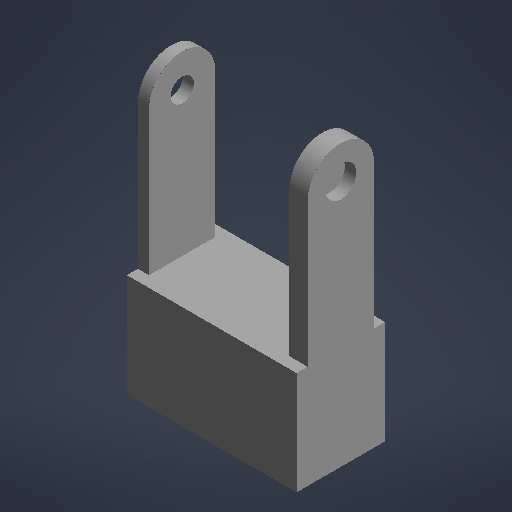
# Autodesk Inventor part: R2_antebrazo_izq
Saved by Autodesk Inventor 2027 (Build 310192060, 192F)
## iProperties
Part Number: R2_antebrazo_izq
Material: Genérico
Document SubType Name: Modelado
Designer: rodri
Appearance: Por defecto
Author: rodri
Autodesk Inventor part; units mm, degrees
ref_plane "Plano de trabajo1" through (0, 0, -9) normal (0, 0, 1) x (1, 0, 0)
sketch "Boceto1" plane through (0, 0, -9) normal (0, 0, 1) x (1, 0, 0)
  line L0 (101.61, -41) -> (106.6, -41)
  line L1 (106.6, -41) -> (106.6, 1)
  line L2 (106.6, 1) -> (101.61, 1)
  line L3 (101.61, 1) -> (101.61, -41)
  constraints: 8 end point, 2 parallel, 1 horizontal, 1 perpendicular
extrude "Extrusión1" add sketch "Boceto1" along normal blind 18
ref_plane "Plano de trabajo2" through (101.61, 0, 0) normal (1, 0, 0) x (0, 1, 0)
sketch "Boceto2" plane through (101.61, 0, 0) normal (1, 0, 0) x (0, 1, 0)
  circle A0 centre (1, 0) radius 9
  constraints: 1 centre point
extrude "Extrusión2" add sketch "Boceto2" along normal blind 4.99
ref_plane "Plano de trabajo3" through (0, 0, -9) normal (0, 0, 1) x (1, 0, 0)
sketch "Boceto3" plane through (0, 0, -9) normal (0, 0, 1) x (1, 0, 0)
  line L0 (60.59, -41) -> (63.59, -41)
  line L1 (63.59, -41) -> (63.59, 1)
  line L2 (63.59, 1) -> (60.59, 1)
  line L3 (60.59, 1) -> (60.59, -41)
  constraints: 8 end point, 2 parallel, 1 horizontal, 1 perpendicular
extrude "Extrusión3" add sketch "Boceto3" along normal blind 18
ref_plane "Plano de trabajo4" through (60.59, 0, 0) normal (1, 0, 0) x (0, 1, 0)
sketch "Boceto4" plane through (60.59, 0, 0) normal (1, 0, 0) x (0, 1, 0)
  circle A0 centre (1, 0) radius 9
  constraints: 1 centre point
extrude "Extrusión4" add sketch "Boceto4" along normal blind 3
ref_plane "Plano de trabajo5" through (0, 0, -12) normal (0, 0, 1) x (1, 0, 0)
sketch "Boceto5" plane through (0, 0, -12) normal (0, 0, 1) x (1, 0, 0)
  line L0 (60.59, -66) -> (106.6, -66)
  line L1 (106.6, -66) -> (106.6, -38)
  line L2 (106.6, -38) -> (60.59, -38)
  line L3 (60.59, -38) -> (60.59, -66)
  constraints: 8 end point, 2 parallel, 1 horizontal, 1 perpendicular
extrude "Extrusión5" add sketch "Boceto5" along normal blind 24
ref_plane "Plano de trabajo6" through (0, 0, -12.1) normal (0, 0, 1) x (1, 0, 0)
sketch "Boceto6" plane through (0, 0, -12.1) normal (0, 0, 1) x (1, 0, 0)
  line L0 (63.59, -62) -> (103.6, -62)
  line L1 (103.6, -62) -> (103.6, -42)
  line L2 (103.6, -42) -> (63.59, -42)
  line L3 (63.59, -42) -> (63.59, -62)
  constraints: 8 end point, 2 parallel, 1 horizontal, 1 perpendicular
extrude "Extrusión6" cut sketch "Boceto6" along normal blind 21.1
ref_plane "Plano de trabajo7" through (103.5, 0, 0) normal (1, 0, 0) x (0, 1, 0)
sketch "Boceto7" plane through (103.5, 0, 0) normal (1, 0, 0) x (0, 1, 0)
  circle A0 centre (1, 0) radius 4.2
  constraints: 1 centre point
extrude "Extrusión7" cut sketch "Boceto7" along normal blind 3.2
ref_plane "Plano de trabajo8" through (60.4, 0, 0) normal (1, 0, 0) x (0, 1, 0)
sketch "Boceto8" plane through (60.4, 0, 0) normal (1, 0, 0) x (0, 1, 0)
  circle A0 centre (1, 0) radius 3.15
  constraints: 1 centre point
extrude "Extrusión8" cut sketch "Boceto8" along normal blind 3.3
